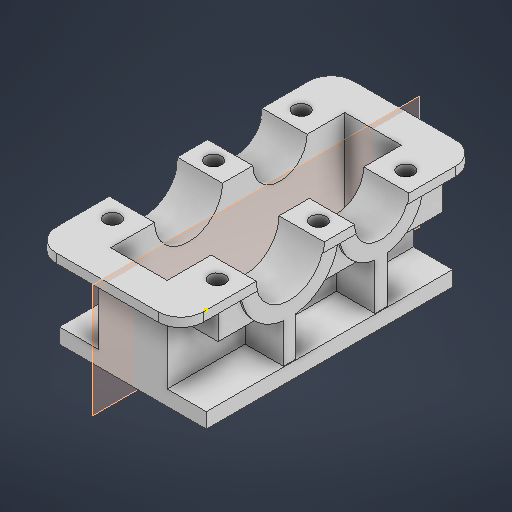
# Autodesk Inventor part: 箱座
Saved by Autodesk Inventor 2026 (Build 300175000, 175)
## iProperties
Created: 2026-08-27
Part Number: 箱座
Material: 常规
Document SubType Name: Modeling
Designer: 14170
Density: 1 g/cm^3
Appearance: 默认
Author: 14170
Autodesk Inventor part; units mm, degrees
ref_plane "YZ Plane" through (0, 0, 0) normal (1, 0, 0) x (0, 1, 0)
ref_plane "XZ Plane" through (0, 0, 0) normal (0, 1, 0) x (-1, 0, 0)
ref_plane "XY Plane" through (0, 0, 0) normal (0, 0, 1) x (1, 0, 0)
sketch "草图1" plane through (0, 0, 0) normal (0, 1, 0) x (-1, 0, 0)
  line L0 (0, 0) -> (0, -326.6)
  line L1 (0, -326.6) -> (195, -326.6)
  line L2 (195, -326.6) -> (195, 0)
  line L3 (195, 0) -> (0, 0)
  dimension "d0" = 326.6
  dimension "d1" = 195
  constraints: 8 end point, 3 perpendicular, 1 vertical
  measures "d0" distance of L0.start L0.end
  measures "d1" distance of L0.end L1.end
extrude "拉伸1" add sketch "草图1" along normal blind 20
sketch "草图2" plane through (0, 20, 0) normal (0, 1, 0) x (1, 0, 0)
  line L0 (-195, 0) -> (0, 0) projected
  line L1 (-52, 0) -> (-52, 326.6)
  line L2 (0, 326.6) -> (-195, 326.6) projected
  line L3 (-143, 326.6) -> (-143, 0)
  line L4 (-143, 0) -> (-52, 0)
  constraints: 6 end point, 3 point on line, 2 vertical, 1 perpendicular
extrude "拉伸2" add sketch "草图2" along normal blind 116.75
sketch "草图3" plane through (0, 136.75, 0) normal (0, 1, 0) x (1, 0, 0)
  line L0 (0, 0) -> (0, -4)
  line L1 (-30, -34) -> (-165, -34)
  line L2 (-195, -4) -> (-195, 0)
  line L3 (0, 0) -> (0, 326.6) projected
  line L4 (0, 0) -> (-195, 0)
  line L5 (0, 326.6) -> (0, 330.6)
  line L6 (-30, 360.6) -> (-165, 360.6)
  line L7 (-195, 326.6) -> (-195, 0) projected
  line L8 (-195, 330.6) -> (-195, 326.6)
  line L9 (-195, 326.6) -> (0, 326.6)
  line L10 (0, 0) -> (0, 326.6)
  line L11 (-195, 326.6) -> (-195, 0)
  line L12 (-195, 0) -> (0, 0)
  arc A0 (0, 330.6) -> (-30, 360.6) centre (-30, 330.6) ccw
  arc A1 (-165, 360.6) -> (-195, 330.6) centre (-165, 330.6) ccw
  arc A2 (-195, -4) -> (-165, -34) centre (-165, -4) ccw
  arc A3 (-30, -34) -> (0, -4) centre (-30, -4) ccw
  point P0 (0, -34)
  point P1 (-195, -34)
  point P2 (0, 360.6)
  point P3 (-195, 360.6)
  dimension "d7" = 34
  dimension "d8" = 34
  dimension "d52" = 30
  constraints: 22 end point, 8 point on circle, 8 point on line, 8 tangent, 7 perpendicular, 4 centre point, 3 equal radius, 3 vertical, 1 collinear
  measures "d7" distance of L0.start point (0, -34)
  measures "d8" distance of L3.end point (0, 360.6)
  measures "d52" radius of A0
extrude "拉伸3" add sketch "草图3" against normal blind 12
sketch "草图4" plane through (0, 136.75, 0) normal (0, 1, 0) x (1, 0, 0)
  line L0 (-52, 326.6) -> (-52, 0) projected
  line L1 (-60, 163.3) -> (-60, 318.6)
  line L2 (-60, 318.6) -> (-135, 318.6)
  line L3 (-135, 318.6) -> (-135, 8)
  line L4 (-135, 8) -> (-60, 8)
  line L5 (-60, 8) -> (-60, 163.3)
  line L6 (0, -4) -> (0, 330.6) projected
  line L7 (-30, 360.6) -> (-165, 360.6) projected
  point P0 (0, 0)
  dimension "d12" = 155.3
  dimension "d13" = 75
  dimension "d14" = 310.6
  dimension "d71" = 60
  dimension "d72" = 42
  constraints: 10 end point, 4 perpendicular, 1 point on line, 1 vertical
  measures "d12" distance of L1.start L1.end
  measures "d13" distance of L1.end L2.end
  measures "d14" distance of L2.end L3.end
  measures "d71" distance between parallel lines of L6 L5
  measures "d72" distance between parallel lines of L7 L2
extrude "拉伸4" cut sketch "草图4" against normal blind 123.75
sketch "草图5" plane through (-143, 20, -326.6) normal (-1, 0, 0) x (0, 0, 1)
  line L0 (-4, 116.75) -> (330.6, 116.75) projected
  arc A0 (38, 116.75) -> (150, 116.75) centre (94, 116.75) ccw
  line L1 (-34, 116.75) -> (-34, 104.75) projected
  arc A1 (58, 116.75) -> (130, 116.75) centre (94, 116.75) ccw
  arc A2 (150.3, 116.75) -> (280.3, 116.75) centre (215.3, 116.75) ccw
  arc A3 (170.3, 116.75) -> (260.3, 116.75) centre (215.3, 116.75) ccw
  line L2 (38, 116.75) -> (280.3, 116.75)
  line L3 (326.6, 0) -> (0, 0) projected
  line L4 (94, 0) -> (102, 0)
  line L5 (102, 0) -> (102, 61.3244)
  line L6 (94, 0) -> (86, 0)
  line L7 (86, 0) -> (86, 61.3244)
  line L8 (215.3, 0) -> (223.3, 0)
  line L9 (223.3, 0) -> (223.3, 52.2442)
  line L10 (215.3, 0) -> (207.3, 0)
  line L11 (207.3, 0) -> (207.3, 52.2442)
  point P0 (326.6, -20)
  point P1 (360.6, 116.75)
  point P2 (-34, 110.75)
  point P3 (58, 116.75)
  dimension "d17" = 112
  dimension "d18" = 128
  dimension "d19" = 72
  dimension "d20" = 130
  dimension "d21" = 121.3
  dimension "d22" = 90
  dimension "d37" = 8
  dimension "d38" = 8
  dimension "d39" = 8
  dimension "d40" = 8
  constraints: 18 end point, 16 point on line, 12 point on circle, 4 centre point, 4 perpendicular, 2 coincident, 1 midpoint
  measures "d17" diameter of A0
  measures "d18" horizontal distance of A0.centre point (-34, 110.75)
  measures "d19" diameter of A1
  measures "d20" diameter of A2
  measures "d21" distance of A2.centre A0.centre
  measures "d22" diameter of A3
  measures "d37" distance of L4.start L4.end
  measures "d38" distance of L4.start L6.end
  measures "d39" distance of L8.start L8.end
  measures "d40" distance of L8.start L10.end
extrude "拉伸5" cut sketch "草图5" against normal through all contours L0 A3
extrude "拉伸6" cut sketch "草图5" along normal through all contours L0 A3
extrude "拉伸7" cut sketch "草图5" against normal through all contours L0 A1
extrude "拉伸8" cut sketch "草图5" along normal through all contours L0 A1
extrude "拉伸9" add sketch "草图5" along normal blind 51 contours L0 A3 A2
extrude "拉伸10" add sketch "草图5" along normal blind 51 contours L0 A1 A0
sketch "草图6" plane through (-52, 20, 0) normal (1, 0, 0) x (0, 0, -1)
  arc A0 (67.9295, 104.75) -> (154.6705, 104.75) centre (111.3, 116.75) ccw projected
  arc A1 (46.3, 116.75) -> (176.3, 116.75) centre (111.3, 116.75) ccw
  arc A2 (198.6589, 104.75) -> (266.5411, 104.75) centre (232.6, 116.75) ccw projected
  arc A3 (176.6, 116.75) -> (288.6, 116.75) centre (232.6, 116.75) ccw
  line L0 (46.3, 116.75) -> (288.6, 116.75)
  line L1 (268.6, 116.75) -> (318.6, 116.75) projected
  arc A4 (66.3, 116.75) -> (156.3, 116.75) centre (111.3, 116.75) ccw
  arc A5 (196.6, 116.75) -> (268.6, 116.75) centre (232.6, 116.75) ccw
  line L2 (326.6, 0) -> (0, 0) projected
  line L3 (111.3, 0) -> (119.3, 0)
  line L4 (119.3, 0) -> (119.3, 52.2442)
  line L5 (111.3, 0) -> (103.3, 0)
  line L6 (103.3, 0) -> (103.3, 52.2442)
  line L7 (232.6, 0) -> (240.6, 0)
  line L8 (240.6, 0) -> (240.6, 61.3244)
  line L9 (232.6, 0) -> (224.6, 0)
  line L10 (224.6, 0) -> (224.6, 61.3244)
  point P0 (0, -20)
  point P1 (266.5411, 104.75)
  dimension "d43" = 8
  dimension "d44" = 8
  dimension "d45" = 8
  dimension "d46" = 8
  constraints: 19 end point, 12 point on circle, 12 point on line, 4 centre point, 4 coincident, 3 perpendicular, 2 concentric, 1 vertical
  measures "d43" distance of L3.start L3.end
  measures "d44" distance of L3.start L5.end
  measures "d45" distance of L7.start L7.end
  measures "d46" distance of L7.start L9.end
extrude "拉伸11" add sketch "草图6" along normal blind 51 contours A0 A4 L0 A1 | A1 L4 L2 L6 | L0 A5 A2 A3 | A3 L8 L2 L10
extrude "拉伸12" add sketch "草图5" along normal blind 51 contours A0 L5 L3 L7 | L11 A2 L9 L3
sketch "草图7" plane through (0, 124.75, 0) normal (0, -1, 0) x (1, 0, 0)
  line L0 (-3.4, -19) -> (-3.4, -316)
  line L1 (-3.4, -316) -> (-52, -316)
  line L2 (-52, -326.6) -> (-52, -287.2992) projected
  line L3 (-52, 0) -> (0, 0) projected
  line L4 (-52, -316) -> (-52, 0)
  line L5 (-3.4, -19) -> (-52, -19)
  dimension "d47" = 297
  constraints: 8 end point, 3 perpendicular, 2 point on line, 1 vertical
  measures "d47" distance of L0.start L0.end
extrude "拉伸13" add sketch "草图7" along normal blind 35.5
ref_plane "工作平面1" through (-97.5, 13, -8) normal (1, 0, 0) x (0, 0, -1)
mirror "镜像1" about plane through (-97.5, 13, -8) normal (1, 0, 0) of "拉伸13"
sketch "草图8" plane through (0, 124.75, -360.6) normal (1, 0, 0) x (0, 0, -1)
  arc A0 (-294.3, 12) -> (-204.3, 12) centre (-249.3, 12) ccw projected
  arc A1 (-294.3, 12) -> (-204.3, 12) centre (-249.3, 12) ccw
  arc A2 (-164, 12) -> (-92, 12) centre (-128, 12) ccw projected
  arc A3 (-164, 12) -> (-92, 12) centre (-128, 12) ccw
  line L0 (-294.3, 12) -> (-92, 12)
  point P0 (-360.6, -124.75)
  point P1 (-164, 12)
  point P2 (-204.3, 12)
  constraints: 4 point on circle, 2 centre point, 2 coincident, 2 end point, 2 point on line, 1 horizontal
extrude "拉伸14" cut sketch "草图8" against normal through all
sketch "草图9" plane through (0, 136.75, 0) normal (0, 1, 0) x (1, 0, 0)
  circle A0 centre (-167, 292.6) radius 10.5
  line L0 (-194, 198.6589) -> (-194, 266.5411) projected
  circle A1 centre (-167, 176.475) radius 10.5
  circle A2 centre (-167, 42.375) radius 10.5
  line L1 (-195, 196.6) -> (-195, 156.3) projected
  line L2 (-195, 66.3) -> (-195, -4) projected
  line L3 (-135, 318.6) -> (-60, 318.6) projected
  line L4 (-97.5, 318.6) -> (-97.5, 8)
  line L5 (-60, 8) -> (-135, 8) projected
  circle A3 centre (-28, 292.6) radius 10.5
  circle A4 centre (-28, 176.475) radius 10.5
  circle A5 centre (-28, 42.375) radius 10.5
  line L6 (0, 156.3) -> (0, 196.6) projected
  line L7 (0, 268.6) -> (0, 330.6) projected
  line L8 (0, -4) -> (0, 66.3) projected
  line L9 (-135, 268.6) -> (-135, 318.6) projected
  line L10 (-135, 156.3) -> (-135, 196.6) projected
  line L11 (-135, 8) -> (-135, 66.3) projected
  line L12 (-60, 318.6) -> (-60, 268.6) projected
  line L13 (-60, 196.6) -> (-60, 156.3) projected
  line L14 (-60, 66.3) -> (-60, 8) projected
  point P0 (0, 0)
  point P1 (-194, 232.6)
  point P2 (0, 176.45)
  point P3 (-60, 293.6)
  point P4 (-60, 176.45)
  dimension "d53" = 21
  dimension "d54" = 60
  dimension "d55" = 21
  dimension "d56" = 21
  dimension "d57" = 134.1
  dimension "d58" = 116.125
  dimension "d61" = 21
  dimension "d62" = 21
  dimension "d63" = 21
  dimension "d64" = 134.1
  dimension "d65" = 116.125
  dimension "d73" = 32
  dimension "d74" = 32
  dimension "d75" = 32
  dimension "d76" = 32
  dimension "d77" = 32
  dimension "d78" = 32
  constraints: 6 centre point, 6 midpoint, 2 end point
  measures "d53" diameter of A0
  measures "d54" vertical distance of point (-194, 232.6) A0.centre
  measures "d55" diameter of A1
  measures "d56" diameter of A2
  measures "d57" distance of A1.centre A2.centre
  measures "d58" distance of A1.centre A0.centre
  measures "d61" diameter of A3
  measures "d62" diameter of A4
  measures "d63" diameter of A5
  measures "d64" distance of A4.centre A5.centre
  measures "d65" distance of A4.centre A3.centre
  measures "d73" distance from line of L9 A0.centre
  measures "d74" distance from line of L10 A1.centre
  measures "d75" distance from line of L11 A2.centre
  measures "d76" horizontal distance of point (-60, 293.6) A3.centre
  measures "d77" distance of point (-60, 176.45) A4.centre
  measures "d78" distance from line of L14 A5.centre
extrude "拉伸15" cut sketch "草图9" against normal blind 60
sketch "草图10" plane through (0, 136.75, 0) normal (0, 1, 0) x (1, 0, 0)
  point P0 (0, 0)
